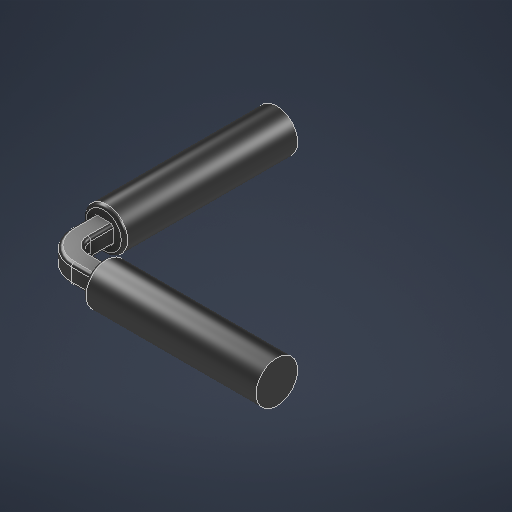
# Autodesk Inventor part: Piston
Saved by Autodesk Inventor 2026.3 (Build 303398000, 398)
## iProperties
Created: 2026-11-02
Part Number: Piston
Material: Stainless Steel
Document SubType Name: Modeling
Designer: ADMIN
Density: 8 g/cm^3
Appearance: Glossy - Black
Author: ADMIN
Autodesk Inventor part; units mm, degrees
ref_plane "XZ Plane" through (0, 0, 0) normal (0, 1, 0) x (-1, 0, 0)
ref_plane "XY Plane" through (0, 0, 0) normal (0, 0, 1) x (1, 0, 0)
sketch "Sketch1" plane through (0, 0, 0) normal (0, 0, 1) x (1, 0, 0)
  circle A0 centre (0, 0) radius 3.25
  dimension "d0" = 6.5
  constraints: 1 centre point, 1 coincident
  measures "d0" diameter of A0
extrude "Extrusion1" add sketch "Sketch1" against normal blind 27
sketch "Sketch3" plane through (0, 0, 0) normal (0, 1, 0) x (-1, 0, 0)
  line L0 (0, 0) -> (0, 3.5)
  line L1 (-3.5, 7) -> (-7, 7)
  arc A0 (0, 3.5) -> (-3.5, 7) centre (-3.5, 3.5) ccw
  point P0 (0, 7)
  dimension "d3" = 7
  dimension "d4" = 7
  dimension "d12" = 3.5
  constraints: 4 end point, 2 point on circle, 2 point on line, 2 tangent, 1 centre point, 1 perpendicular, 1 vertical
  measures "d3" distance of L0.start point (0, 7)
  measures "d4" distance of point (0, 7) L1.end
  measures "d12" radius of A0
ref_plane "Work Plane1" through (7, 0, 7) normal (1, 0, 0) x (0, 1, 0)
sketch "Sketch5" plane through (7, 0, 7) normal (1, 0, 0) x (0, 1, 0)
  line L0 (3.25, -7) -> (-3.25, -7) projected
  circle A0 centre (0, 0) radius 3.25
  point P0 (0, -7)
  point P1 (0, -7)
  dimension "d6" = 7
  dimension "d7" = 6.5
  constraints: 1 centre point, 1 midpoint, 1 vertical alignment
  measures "d6" distance of point (0, -7) A0.centre
  measures "d7" diameter of A0
extrude "Extrusion2" add sketch "Sketch5" along normal blind 27
sketch "Sketch6" plane through (0, 0, 0) normal (0, 0, 1) x (1, 0, 0)
  line L0 (-1.5, 1.5) -> (1.5, 1.5)
  line L1 (1.5, 1.5) -> (1.5, -1.5)
  line L2 (1.5, -1.5) -> (-1.5, -1.5)
  line L3 (-1.5, -1.5) -> (-1.5, 1.5)
  point P0 (0, 0)
  point P1 (1.5, 0)
  point P2 (0, 1.5)
  dimension "d10" = 3
  dimension "d11" = 3
  constraints: 8 end point, 2 midpoint, 2 parallel, 1 horizontal, 1 horizontal alignment, 1 perpendicular, 1 vertical alignment
  measures "d10" distance of L0.end L1.end
  measures "d11" distance of L1.end L2.end
sweep "Sweep1" add profiles "Sketch6" path "Sketch3" path curves L0 A0 L1
fillet "Fillet1" radius 0.5 2 edges at (-3.25, 0, 0) (7, -3.25, 7)
fillet "Fillet2" radius 0.5 12 edges at (5.25, -1.5, 8.5) (-1.5, -1.5, 1.75) (-0.0355, -1.5, 7.0355) (5.25, 1.5, 8.5) (-1.5, 1.5, 1.75) (-0.0355, 1.5, 7.0355) (2.0858, 1.5, 4.9142) (1.5, 1.5, 1.75) (5.25, 1.5, 5.5) (2.0858, -1.5, 4.9142) (1.5, -1.5, 1.75) (5.25, -1.5, 5.5)
body "Solid1"
